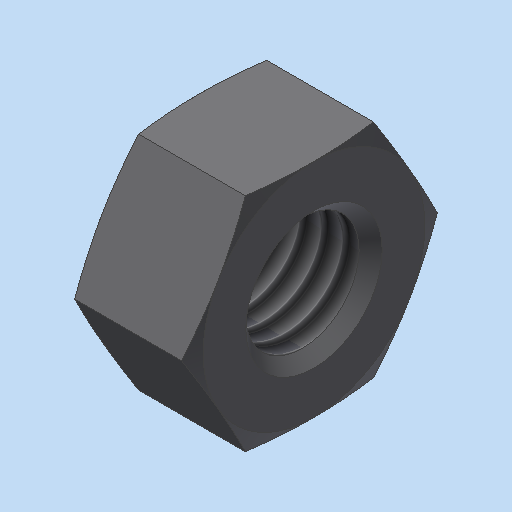
# Autodesk Inventor part: Sechskantmutter_ISO_4032___M8
Saved by Autodesk Inventor 2023.3 (Build 273359000, 359)
## iProperties
Shininess: 64.0
Length Units: 11269
Angle Units: 11279
Time Units: 11290
Mass Units: 11283
Length Display Precision: 3
Angle Display Precision: 2
Compacted: True
Part Number: Sechskantmutter_ISO_4032___M8
Document SubType Name: Modeling
Created: 2004-03-22
Material: xStahl_AnP_Dummymaterial
Description: =<RBPARTNOTITLE2>
Vendor: NORM8
Designer: S.Riedelsheimer
Manufacturer: Standard
Standards Organization: Custom
Density: 7.85 g/cm^3
Appearance: Stahl - normal AnP
Mass: 5.86278 g
Surface Area: 6.48818 cm^2
Volume: 0.746851 cm^3
Density: 0.0
Volumn: 0.0
Area: 0.0
PropertySet Name: Model Information
Control State: 0
Master: False
Checked Out: False
CNS_NB: Sechskantmutter ISO 4032 - M 8
CNS_NN: ISO 4032
CNS_NT: Sechskantmutter, Typ 1
CNS_NBSYN: Sechskantmutter ISO 4032 - $NENN.
CNS_LINA: Sechskantmutter ISO 4032 - M 8
CNS_NENN: M 8
CNS_D: 8.000
CNS_D1: 6.647
CNS_P: 1.250
CNS_M: 6.800
CNS_S: 13.000
CNS_KT: X
PSOL_IDENT_0: {C:\partsolutions8\data\23d-libs\bosch_bamberg\muttern\sechskantmuttern\din_iso_4032.prj},166 {M=Nen
PSOL_IDENT_1: ngewinde},{VTYP=3D},{NB=Sechskantmutter ISO 4032 - M 8},{NN=ISO 4032},{DATE=26.11.2003},{GEOMDATE=26
PSOL_IDENT_2: .11.2003},{VERSION=v2},{LINEID=80},{LINESUBID=-1},{WBVAR=}  {NB=Sechskantmutter ISO 4032 - M 8},{LIN
PSOL_IDENT_3: A=Sechskantmutter ISO 4032 - M 8},{KT=X},{IDNR=},{NENN=M 8},{D=8.000},{D1=6.647},{P=1.250},{M=6.800}
PSOL_IDENT_4: ,{S=13.000}
RBPARTNOTITLE1: Hexagon regular nuts (style 1)
RBPARTNOTITLE2: Sechskantmuttern (Typ 1)
RBDRAWINGMISSINGSPEC: --
AnP_Kategorie: 5
RBPARTMADEOF: ISO 4032 - M8 - 8.8 - verzinkt
Title: Sechskantmutter ISO 4032 - M 8
Author: S.Riedelsheimer
Keywords: =<RBPARTMADEOF>
Comments: =<RBSURFACE2>
Revision Number: 01
Autodesk Inventor part; units mm, degrees
sketch "Sketch_1" plane through (0, 0, 0) normal (0, 1, 0) x (-1, 0, 0)
  line L0 (0, 0) -> (-6.8, 0)
  line L1 (0, 6.5) -> (-3.4, 19.189)
  line L2 (-3.4, 19.189) -> (-6.8, 6.5)
  line L3 (-6.8, 6.5) -> (-6.8, 4)
  line L4 (-6.8, 4) -> (-6.1235, 3.3235)
  line L5 (-6.1235, 3.3235) -> (-0.6765, 3.3235)
  line L6 (-0.6765, 3.3235) -> (0, 4)
  line L7 (0, 4) -> (0, 6.5)
  constraints: 16 end point
revolve "Drehung1" add sketch "Sketch_1" angle 360 about axis through (0, 0, 0) along (-1, 0, 0)
thread "Gewinde1" size "M8x1.25" class "6H" standard "ANSI Metric M Profile" length 6.8
sketch "Sketch_2" plane through (0, 0, 0) normal (1, 0, 0) x (0, 1, 0)
  line L0 (-26, 26) -> (-26, -26)
  line L1 (-26, -26) -> (26, -26)
  line L2 (26, -26) -> (26, 26)
  line L3 (26, 26) -> (-26, 26)
  line L4 (-3.7528, 6.5) -> (-7.5056, 0)
  line L5 (-7.5056, 0) -> (-3.7528, -6.5)
  line L6 (-3.7528, -6.5) -> (3.7528, -6.5)
  line L7 (3.7528, -6.5) -> (7.5056, 0)
  line L8 (7.5056, 0) -> (3.7528, 6.5)
  line L9 (3.7528, 6.5) -> (-3.7528, 6.5)
  constraints: 20 end point
extrude "Extrusion1" cut sketch "Sketch_2" along normal mid plane 15.6
ref_plane "IP1_XY" through (0, 0, 0) normal (1, 0, 0) x (0, 0, -1)
ref_plane "IP1_YZ" through (0, 0, 0) normal (0, 0, -1) x (0, 1, 0)
ref_plane "IP2_XY" through (6.8, 0, 0) normal (1, 0, 0) x (0, 0, -1)
ref_plane "IP2_YZ" through (6.8, 0, 0) normal (0, 0, -1) x (0, 1, 0)
